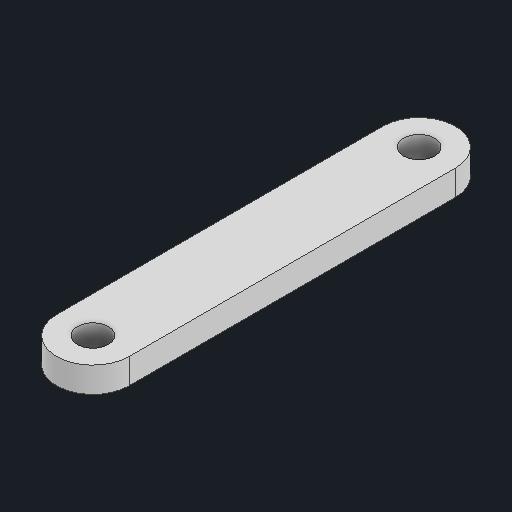
# Autodesk Inventor part: LowerFollowerLink
Saved by Autodesk Inventor 2027.1 (Build 311270010, 270A)
## iProperties
Created: 2026-10-23
Part Number: LowerFollowerLink
Material: Generic
Document SubType Name: Modeling
Designer: HP
Density: 1 g/cm^3
Appearance: Default
Author: HP
Autodesk Inventor part; units mm, degrees
ref_plane "YZ Plane" through (0, 0, 0) normal (1, 0, 0) x (0, 1, 0)
ref_plane "XZ Plane" through (0, 0, 0) normal (0, 1, 0) x (-1, 0, 0)
ref_plane "XY Plane" through (0, 0, 0) normal (0, 0, 1) x (1, 0, 0)
sketch "Sketch1" plane through (0, 0, 0) normal (0, 1, 0) x (-1, 0, 0)
  line L0 (5, -5) -> (5, -50)
  line L1 (-5, -5) -> (-5, -50)
  arc A0 (-5, -50) -> (5, -50) centre (0, -50) ccw
  arc A1 (5, -5) -> (-5, -5) centre (0, -5) ccw
  circle A2 centre (0, -5) radius 2.15
  circle A3 centre (0, -50) radius 2.15
  point P0 (0, 0)
  point P1 (0, 0)
  dimension "d6" = 10
  dimension "d7" = 45
  dimension "d8" = 4.3
  dimension "d9" = 4.3
  constraints: 5 point on circle, 4 centre point, 4 end point, 4 tangent, 3 coincident, 2 vertical
  measures "d6" distance of L1.end L0.end
  measures "d7" distance of L1.start L1.end
  measures "d8" diameter of A2
  measures "d9" diameter of A3
extrude "Extrusion2" add sketch "Sketch1" along normal blind 3.5
body "Solid2"
